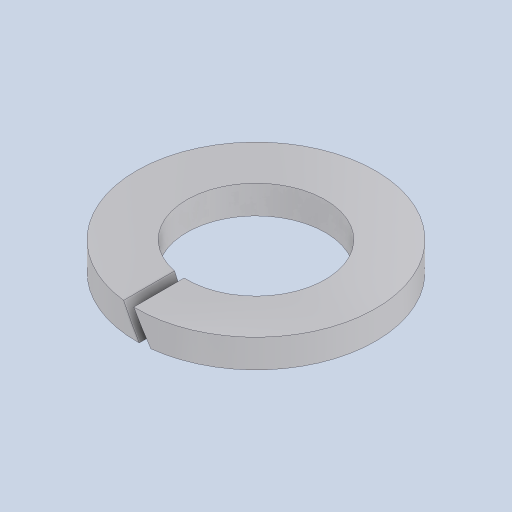
# Autodesk Inventor part: Arruela de pressão DIN 127 B M4
Saved by Autodesk Inventor 2024.3 (Build 283343000, 343)
## iProperties
Created: 2025-02-01
Part Number: Arruela de pressão DIN 127 B M4
Material: Aço, carbono
Document SubType Name: Modeling
Designer: Cliente
Density: 7.85 g/cm^3
Appearance: Semipolido
Mass: 0.209152 g
Surface Area: 0.958452 cm^2
Volume: 0.0266436 cm^3
Author: Cliente
Autodesk Inventor part; units mm, degrees
ref_plane "YZ Plane" through (0, 0, 0) normal (1, 0, 0) x (0, 1, 0)
ref_plane "XZ Plane" through (0, 0, 0) normal (0, 1, 0) x (-1, 0, 0)
sketch "Esboço1" plane through (0, 0, 0) normal (0, 1, 0) x (-1, 0, 0)
  circle A0 centre (0, 0) radius 3.8
  circle A1 centre (0, 0) radius 2.2
  dimension "d1" = 7.6
  dimension "d2" = 4.4
  constraints: 2 centre point, 2 coincident
  measures "d1" diameter of A0
  measures "d2" diameter of A1
extrude "Extrusão1" add sketch "Esboço1" along normal mid plane 0.9
ref_plane "Plano de trabalho1" through (0, 0, 3.8) normal (0, 0, 1) x (1, 0, 0)
sketch "Esboço2" plane through (0, 0, 3.8) normal (0, 0, 1) x (1, 0, 0)
  line L0 (3.8, 0.45) -> (-3.8, 0.45) projected
  line L1 (0.5049, -0.5745) -> (-0.2451, 0.7245)
  line L2 (-0.2451, 0.7245) -> (-0.5049, 0.5745)
  line L3 (-0.5049, 0.5745) -> (0.2451, -0.7245)
  line L4 (0.2451, -0.7245) -> (0.5049, -0.5745)
  line L5 (0.5049, -0.5745) -> (-0.5049, 0.5745) construction
  line L6 (-0.2451, 0.7245) -> (0.2451, -0.7245) construction
  line L7 (0.5049, -0.5745) -> (2.0049, -0.5745) construction
  line L8 (0, 0.45) -> (0, -0.45)
  line L9 (2.2, -0.45) -> (-2.2, -0.45) projected
  point P0 (0, 0)
  point P1 (0, 0)
  point P2 (0, 0)
  dimension "d5" = 1.5
  dimension "d6" = 120
  dimension "d7" = 0.3
  constraints: 16 end point, 6 midpoint, 2 parallel, 1 equal length, 1 horizontal, 1 perpendicular
  measures "d5" distance of L1.start L1.end
  measures "d6" angle of L7 L1
  measures "d7" distance of L2.end L1.end
extrude "Extrusão2" cut sketch "Esboço2" against normal blind 2 contours L1 L8 L3 L0 | L0 L3 L2 L1 | L1 L9 L3 L8 | L1 L4 L3 L9
